Bottom Plate W Walls (Autodesk Fusion 360 design; units mm, degrees)
Autodesk Fusion 360 part; units mm, degrees
sketch "Sketch1" plane through (0, 0, 0) normal (0, -1, 0) x (1, 0, 0) in component "Component"
  arc A0 (31, 16.8) -> (26.6, 19) centre (26.6, 13.5) ccw
  line L0 (26.6, 19) -> (-31.5, 19)
  arc A1 (-31.5, 19) -> (-35.9, 16.8) centre (-31.5, 13.5) ccw
  arc A2 (-35.9, 16.8) -> (-37.5, 12) centre (-29.5, 12) ccw
  line L1 (-37.5, 12) -> (-37.5, -12)
  arc A3 (-37.5, -12) -> (-29.5, -20) centre (-29.5, -12) ccw
  line L2 (-29.5, -20) -> (24.6, -20)
  arc A4 (24.6, -20) -> (32.6, -12) centre (24.6, -12) ccw
  line L3 (32.6, -12) -> (32.6, 12)
  arc A5 (32.6, 12) -> (31, 16.8) centre (24.6, 12) ccw
  circle A6 centre (-29, 11.5) radius 1.375
  circle A7 centre (-29, -11.5) radius 1.375
  circle A8 centre (29, -11.5) radius 1.375
  circle A9 centre (29, 11.5) radius 1.375
  line L4 (-27.8453, 9.5) -> (-26.6906, 11.5)
  line L5 (-26.6906, 11.5) -> (-27.8453, 13.5)
  line L6 (-27.8453, 13.5) -> (-30.1547, 13.5)
  line L7 (-30.1547, 13.5) -> (-31.3094, 11.5)
  line L8 (-31.3094, 11.5) -> (-30.1547, 9.5)
  line L9 (-30.1547, 9.5) -> (-27.8453, 9.5)
  line L10 (-27.8453, -13.5) -> (-26.6906, -11.5)
  line L11 (-26.6906, -11.5) -> (-27.8453, -9.5)
  line L12 (-27.8453, -9.5) -> (-30.1547, -9.5)
  line L13 (-30.1547, -9.5) -> (-31.3094, -11.5)
  line L14 (-31.3094, -11.5) -> (-30.1547, -13.5)
  line L15 (-30.1547, -13.5) -> (-27.8453, -13.5)
  line L16 (30.1547, -13.5) -> (31.3094, -11.5)
  line L17 (31.3094, -11.5) -> (30.1547, -9.5)
  line L18 (30.1547, -9.5) -> (27.8453, -9.5)
  line L19 (27.8453, -9.5) -> (26.6906, -11.5)
  line L20 (26.6906, -11.5) -> (27.8453, -13.5)
  line L21 (27.8453, -13.5) -> (30.1547, -13.5)
  line L22 (30.1547, 9.5) -> (31.3094, 11.5)
  line L23 (31.3094, 11.5) -> (30.1547, 13.5)
  line L24 (30.1547, 13.5) -> (27.8453, 13.5)
  line L25 (27.8453, 13.5) -> (26.6906, 11.5)
  line L26 (26.6906, 11.5) -> (27.8453, 9.5)
  line L27 (27.8453, 9.5) -> (30.1547, 9.5)
  point P0 (-29, 11.5)
  point P1 (-29, -11.5)
  point P2 (29, -11.5)
  point P3 (29, 11.5)
  dimension "d1" = 2.75
  dimension "d2" = 2.75
  dimension "d3" = 2.75
  dimension "d4" = 2.75
  constraint coincident P0 A6.centre
  constraint coincident P1 A7.centre
  constraint coincident P2 A8.centre
  constraint coincident P3 A9.centre
  measures "d1" diameter of A6
  measures "d2" diameter of A7
  measures "d3" diameter of A8
  measures "d4" diameter of A9
extrude "Extrude1" add sketch "Sketch1" along normal blind 1 contours A0 L0 A1 A2 L1 A3 L2 A4 L3 A5 in component "Component"
sketch "Sketch2" plane through (0, 0, 0) normal (0, 1, 0) x (-1, 0, 0) in component "Component"
  line L0 (-27.8453, 9.5) -> (-30.1547, 9.5)
  line L1 (-30.1547, 9.5) -> (-31.3094, 11.5)
  line L2 (-31.3094, 11.5) -> (-30.1547, 13.5)
  line L3 (-30.1547, 13.5) -> (-27.8453, 13.5)
  line L4 (-27.8453, 13.5) -> (-26.6906, 11.5)
  line L5 (-26.6906, 11.5) -> (-27.8453, 9.5)
  line L6 (-27.8453, -13.5) -> (-30.1547, -13.5)
  line L7 (-30.1547, -13.5) -> (-31.3094, -11.5)
  line L8 (-31.3094, -11.5) -> (-30.1547, -9.5)
  line L9 (-30.1547, -9.5) -> (-27.8453, -9.5)
  line L10 (-27.8453, -9.5) -> (-26.6906, -11.5)
  line L11 (-26.6906, -11.5) -> (-27.8453, -13.5)
  line L12 (30.1547, 9.5) -> (27.8453, 9.5)
  line L13 (27.8453, 9.5) -> (26.6906, 11.5)
  line L14 (26.6906, 11.5) -> (27.8453, 13.5)
  line L15 (27.8453, 13.5) -> (30.1547, 13.5)
  line L16 (30.1547, 13.5) -> (31.3094, 11.5)
  line L17 (31.3094, 11.5) -> (30.1547, 9.5)
  line L18 (30.1547, -13.5) -> (27.8453, -13.5)
  line L19 (27.8453, -13.5) -> (26.6906, -11.5)
  line L20 (26.6906, -11.5) -> (27.8453, -9.5)
  line L21 (27.8453, -9.5) -> (30.1547, -9.5)
  line L22 (30.1547, -9.5) -> (31.3094, -11.5)
  line L23 (31.3094, -11.5) -> (30.1547, -13.5)
  arc A0 (-31, 16.8) -> (-32.6, 12) centre (-24.6, 12) ccw
  line L24 (-32.6, 12) -> (-32.6, -12)
  arc A1 (-32.6, -12) -> (-24.6, -20) centre (-24.6, -12) ccw
  line L25 (-24.6, -20) -> (29.5, -20)
  arc A2 (29.5, -20) -> (37.5, -12) centre (29.5, -12) ccw
  line L26 (37.5, -12) -> (37.5, 12)
  arc A3 (37.5, 12) -> (35.9, 16.8) centre (29.5, 12) ccw
  arc A4 (35.9, 16.8) -> (31.5, 19) centre (31.5, 13.5) ccw
  line L27 (31.5, 19) -> (-26.6, 19)
  arc A5 (-26.6, 19) -> (-31, 16.8) centre (-26.6, 13.5) ccw
  circle A6 centre (29, 11.5) radius 1.375
  circle A7 centre (29, -11.5) radius 1.375
  circle A8 centre (-29, -11.5) radius 1.375
  circle A9 centre (-29, 11.5) radius 1.375
  dimension "d7" = 2.75
  dimension "d8" = 2.75
  dimension "d9" = 2.75
  dimension "d10" = 2.75
  measures "d7" diameter of A6
  measures "d8" diameter of A7
  measures "d9" diameter of A8
  measures "d10" diameter of A9
extrude "Extrude2" add sketch "Sketch2" along normal blind 1 contours L0 L1 L2 L3 L4 L5 | L6 L7 L8 L9 L10 L11 | L12 L13 L14 L15 L16 L17 | L18 L19 L20 L21 L22 L23 | A0 L24 A1 L25 A2 L26 A3 A4 L27 A5 in component "Component"
sketch "Sketch3" plane through (0, 1, 0) normal (0, 1, 0) x (-1, 0, 0) in component "Component"
  circle A0 centre (-29, -11.5) radius 1.375
  circle A1 centre (-29, 11.5) radius 1.375
  circle A2 centre (29, 11.5) radius 1.375
  circle A3 centre (29, -11.5) radius 1.375
  arc A4 (-26.6, 19) -> (-31, 16.8) centre (-26.6, 13.5) ccw
  arc A5 (-31, 16.8) -> (-32.6, 12) centre (-24.6, 12) ccw
  line L0 (-32.6, 12) -> (-32.6, -12)
  arc A6 (-32.6, -12) -> (-24.6, -20) centre (-24.6, -12) ccw
  line L1 (-24.6, -20) -> (29.5, -20)
  arc A7 (29.5, -20) -> (37.5, -12) centre (29.5, -12) ccw
  line L2 (37.5, -12) -> (37.5, 12)
  arc A8 (37.5, 12) -> (35.9, 16.8) centre (29.5, 12) ccw
  arc A9 (35.9, 16.8) -> (31.5, 19) centre (31.5, 13.5) ccw
  line L3 (31.5, 19) -> (-26.6, 19)
  circle A10 centre (29, 11.5) radius 1.875
  circle A11 centre (29, -11.5) radius 1.875
  circle A12 centre (-29, -11.5) radius 1.875
  circle A13 centre (-29, 11.5) radius 1.875
  dimension "d13" = 3.75
  dimension "d14" = 3.75
  dimension "d15" = 3.75
  dimension "d16" = 3.75
  constraint concentric A2 A10
  constraint concentric A3 A11
  constraint concentric A0 A12
  constraint concentric A1 A13
  measures "d13" diameter of A10
  measures "d14" diameter of A11
  measures "d15" diameter of A12
  measures "d16" diameter of A13
extrude "Extrude3" add sketch "Sketch3" along normal blind 0.5 contours A10 | A11 | A12 | A13 in component "Component"
sketch "Sketch4" plane through (0, 1, 0) normal (0, 1, 0) x (-1, 0, 0) in component "Component"
  circle A0 centre (-29, 11.5) radius 1.875
  circle A1 centre (29, 11.5) radius 1.875
  circle A2 centre (-29, -11.5) radius 1.875
  circle A3 centre (29, -11.5) radius 1.875
  arc A4 (-26.6, 19) -> (-31, 16.8) centre (-26.6, 13.5) ccw
  arc A5 (-31, 16.8) -> (-32.6, 12) centre (-24.6, 12) ccw
  line L0 (-32.6, 12) -> (-32.6, -12)
  arc A6 (-32.6, -12) -> (-24.6, -20) centre (-24.6, -12) ccw
  line L1 (-24.6, -20) -> (29.5, -20)
  arc A7 (29.5, -20) -> (37.5, -12) centre (29.5, -12) ccw
  line L2 (37.5, -12) -> (37.5, 12)
  arc A8 (37.5, 12) -> (35.9, 16.8) centre (29.5, 12) ccw
  arc A9 (35.9, 16.8) -> (31.5, 19) centre (31.5, 13.5) ccw
  line L3 (31.5, 19) -> (-26.6, 19)
  circle A10 centre (33.9393, 16.4393) radius 1
  circle A11 centre (33.9393, 16.4393) radius 1
  circle A12 centre (18.1946, 16.4393) radius 1
  circle A13 centre (18.1946, 16.4393) radius 1
  circle A14 centre (2.4498, 16.4393) radius 1
  circle A15 centre (2.4498, 16.4393) radius 1
  circle A16 centre (-13.2943, 16.4393) radius 1
  circle A17 centre (-13.2943, 16.4393) radius 1
  circle A18 centre (-29.0393, 16.4393) radius 1
  circle A19 centre (-29.0393, 16.4393) radius 1
  circle A20 centre (-29.0393, -16.4393) radius 1
  circle A21 centre (-29.0393, -16.4393) radius 1
  circle A22 centre (33.9393, -16.4393) radius 1
  circle A23 centre (33.9393, -16.4393) radius 1
extrude "Extrude4" add sketch "Sketch4" along normal blind 1 contours A10 A11 | A12 A13 | A14 A15 | A16 A17 | A18 A19 | A20 A21 | A22 A23 in component "Component"
fillet "Fillet1" radius 1 7 edges at (-33.007, 2, -16.801) (-33.007, 2, 16.0777) (-17.2623, 2, 16.0777) (-1.5175, 2, 16.0777) (14.2267, 2, 16.0777) (29.9717, 2, 16.0777) (29.9717, 2, -16.801) in component "Component"
component "Component" placed x (1, 0, 0) y (0, 1, 0) z (0, 0, 1) at (0, 0, 0)
